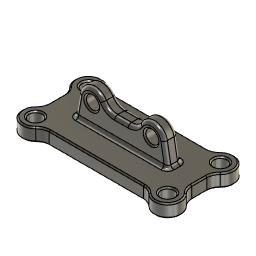
Simulation Set Up (Autodesk Fusion 360 design; units mm, degrees)
Autodesk Fusion 360 part; units mm, degrees
sketch "Sketch1" plane through (0, 0, 0) normal (0, 0, 1) x (1, 0, 0)
  line L0 (63.5, -25.4) -> (-63.5, -25.4) construction
  line L1 (-63.5, -25.4) -> (-63.5, 25.4) construction
  line L2 (-63.5, 25.4) -> (63.5, 25.4) construction
  line L3 (63.5, 25.4) -> (63.5, -25.4) construction
  line L4 (63.5, -25.4) -> (-63.5, 25.4) construction
  line L5 (-63.5, -25.4) -> (63.5, 25.4) construction
  circle A0 centre (-63.5, 25.4) radius 12.7
  circle A1 centre (-63.5, -25.4) radius 12.7
  circle A2 centre (63.5, -25.4) radius 12.7
  circle A3 centre (63.5, 25.4) radius 12.7
  line L6 (-51.8603, 30.48) -> (51.8603, 30.48)
  line L7 (68.58, 13.7603) -> (68.58, -13.7603)
  line L8 (51.8603, -30.48) -> (-51.8603, -30.48)
  line L9 (-68.58, -13.7603) -> (-68.58, 13.7603)
  dimension "d1" = 127
  dimension "d2" = 50.8
  dimension "d3" = 25.4
  dimension "d4" = 5.08
  dimension "d5" = 5.08
  dimension "d6" = 5.08
  dimension "d7" = 5.08
  constraint horizontal L0
  constraint perpendicular L0 L1
  constraint parallel L0 L2
  constraint parallel L1 L3
  constraint coincident L4 origin
  constraint coincident L5 origin
  constraint coincident L1.end L2.start
  constraint coincident L0.end L1.start
  constraint coincident L0.start L3.end
  constraint coincident L2.end L3.start
  constraint equal A0 A1
  constraint equal A0 A3
  constraint equal A0 A2
  constraint coincident A0 L6.start
  constraint coincident A3 L6.end
  constraint horizontal L6
  constraint coincident A3 L7.start
  constraint coincident A2 L7.end
  constraint perpendicular L6 L7
  constraint coincident A2 L8.start
  constraint coincident A1 L8.end
  constraint coincident A1 L9.start
  constraint coincident A0 L9.end
  constraint perpendicular L8 L9
  constraint horizontal L8
  measures "d1" distance of L1.end L2.end
  measures "d2" distance of L0.end L1.end
  measures "d3" diameter of A0
  measures "d4" distance of L0 L8
  measures "d5" distance of L2 L6
  measures "d6" distance of L3 L7
  measures "d7" distance of L1 L9
extrude "Extrude1" add sketch "Sketch1" along normal blind 12.7
sketch "Sketch2" plane through (0, 0, 0) normal (0, 1, 0) x (1, 0, 0)
  line L0 (0, 0) -> (0, -31.75) construction
  line L1 (-28.575, -31.75) -> (28.575, -31.75)
  circle A0 centre (28.575, -31.75) radius 12.7
  circle A1 centre (-28.575, -31.75) radius 12.7
  line L2 (-68.58, -12.7) -> (68.58, -12.7)
  line L3 (-41.0821, -33.9553) -> (-44.8299, -12.7)
  line L4 (41.0821, -33.9553) -> (44.8299, -12.7)
  dimension "d10" = 31.75
  dimension "d11" = 57.15
  dimension "d12" = 25.4
  dimension "d13" = 100
  dimension "d14" = 100
  constraint coincident L0.start origin
  constraint vertical L0
  constraint horizontal L1
  constraint midpoint L0.end L1
  constraint coincident L1.end A0.centre
  constraint coincident L1.start A1.centre
  constraint equal A0 A1
  constraint coincident A1 L3.start
  constraint coincident L2 L3.end
  constraint coincident A0 L4.start
  constraint coincident L2 L4.end
  constraint tangent A1 L3
  constraint tangent A0 L4
  measures "d10" distance of L0.start L0.end
  measures "d11" distance of L1.start L1.end
  measures "d12" diameter of A0
  measures "d13" angle of L1 L4
  measures "d14" angle of L1 L3
extrude "Extrude2" add sketch "Sketch2" along normal mid plane 12.7
sketch "Sketch3" plane through (0, 0, 0) normal (0, 1, 0) x (1, 0, 0)
  arc A0 (15.875, -31.75) -> (41.0821, -33.9553) centre (28.575, -31.75) ccw
  arc A1 (-41.0821, -33.9553) -> (-15.875, -31.75) centre (-28.575, -31.75) ccw
  circle A2 centre (28.575, -31.75) radius 6.35
  circle A3 centre (-28.575, -31.75) radius 6.35
  dimension "d17" = 12.7
  constraint concentric A0 A2
  constraint concentric A1 A3
  constraint equal A2 A3
  measures "d17" diameter of A3
extrude "Extrude3" cut sketch "Sketch3" along normal through all and the other way through all
sketch "Sketch4" plane through (0, 0, 0) normal (0, 0, 1) x (1, 0, 0)
  arc A0 (-51.8603, 30.48) -> (-68.58, 13.7603) centre (-63.5, 25.4) ccw
  arc A1 (-68.58, -13.7603) -> (-51.8603, -30.48) centre (-63.5, -25.4) ccw
  arc A2 (51.8603, -30.48) -> (68.58, -13.7603) centre (63.5, -25.4) ccw
  arc A3 (68.58, 13.7603) -> (51.8603, 30.48) centre (63.5, 25.4) ccw
  circle A4 centre (-63.5, 25.4) radius 6.35
  circle A5 centre (-63.5, -25.4) radius 6.35
  circle A6 centre (63.5, -25.4) radius 6.35
  circle A7 centre (63.5, 25.4) radius 6.35
  dimension "d19" = 12.7
  constraint concentric A0 A4
  constraint concentric A1 A5
  constraint concentric A2 A6
  constraint concentric A3 A7
  constraint equal A4 A5
  constraint equal A4 A7
  constraint equal A4 A6
  measures "d19" diameter of A4
extrude "Extrude4" cut sketch "Sketch4" along normal through all
fillet "Fillet1" radius 12.7 10 edges at (51.8603, -30.48, 6.35) (68.58, -13.7603, 6.35) (68.58, 13.7603, 6.35) (51.8603, 30.48, 6.35) (-51.8603, -30.48, 6.35) (-68.58, -13.7603, 6.35) (-68.58, 13.7603, 6.35) (-51.8603, 30.48, 6.35) (-15.875, 0, 31.75) (15.875, 0, 31.75)
fillet "Fillet2" radius 3.175 14 edges at (42.956, -6.35, 23.3277) (30.7803, -6.35, 44.2571) (12.928, -6.35, 33.4515) (0, -6.35, 31.75) (-12.928, -6.35, 33.4515) (-30.7803, -6.35, 44.2571) (-42.956, -6.35, 23.3277) (-42.956, 6.35, 23.3277) (-30.7803, 6.35, 44.2571) (-12.928, 6.35, 33.4515) (0, 6.35, 31.75) (12.928, 6.35, 33.4515) (30.7803, 6.35, 44.2571) (42.956, 6.35, 23.3277)
fillet "Fillet3" radius 3.175 8 edges at (-43.8857, -5.4201, 12.7) (-44.8299, 0, 12.7) (-43.8857, 5.4201, 12.7) (0, 6.35, 12.7) (43.8857, 5.4201, 12.7) (44.8299, 0, 12.7) (43.8857, -5.4201, 12.7) (0, -6.35, 12.7)
chamfer "Chamfer1" distance 1.27 angle 45 40 edges at (-68.58, 0, 12.7) (-69.5712, -12.1795, 12.7) (-72.4803, -34.3803, 12.7) (-50.2795, -31.4712, 12.7) (0, -30.48, 12.7) (50.2795, -31.4712, 12.7) (72.4803, -34.3803, 12.7) (69.5712, -12.1795, 12.7) (68.58, 0, 12.7) (69.5712, 12.1795, 12.7) (72.4803, 34.3803, 12.7) (50.2795, 31.4712, 12.7) (0, 30.48, 12.7) (-50.2795, 31.4712, 12.7) (-72.4803, 34.3803, 12.7) (-69.5712, 12.1795, 12.7) (-68.58, 0, 0) (-69.5712, 12.1795, 0) (-72.4803, 34.3803, 0) (-50.2795, 31.4712, 0) (0, 30.48, 0) (50.2795, 31.4712, 0) (72.4803, 34.3803, 0) (69.5712, 12.1795, 0) (68.58, 0, 0) (69.5712, -12.1795, 0) (72.4803, -34.3803, 0) (50.2795, -31.4712, 0) (0, -30.48, 0) (-50.2795, -31.4712, 0) (-72.4803, -34.3803, 0) (-69.5712, -12.1795, 0) (-69.4203, 27.6963, 12.7) (-69.4203, -23.1037, 12.7) (57.5797, -23.1037, 12.7) (57.5797, 27.6963, 12.7) (22.6547, -6.35, 34.0463) (22.6547, 6.35, 29.4537) (-34.4953, -6.35, 34.0463) (-34.4953, 6.35, 29.4537)
equation "d5 = d4"
equation "d6 = d4"
equation "d7 = d4"
equation "d14 = d13"
